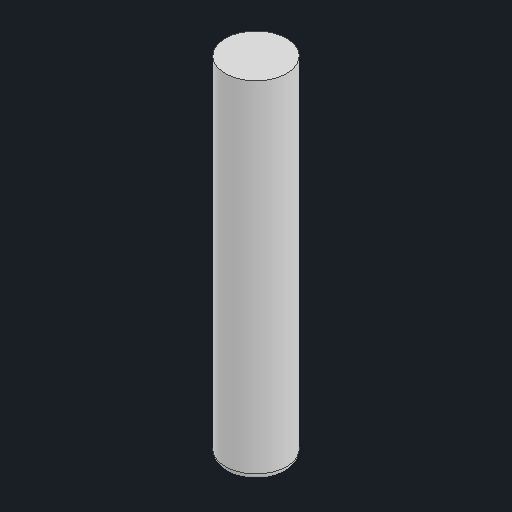
# Autodesk Inventor part: thigh-bone
Saved by Autodesk Inventor 2026.2 (Build 302298010, 298A)
## iProperties
Created: 2026-10-22
Part Number: thigh-bone
Material: Generic
Document SubType Name: Modeling
Designer: user
Density: 1 g/cm^3
Appearance: Default
Mass: 119.992 g
Surface Area: 173.105 cm^2
Volume: 119.992 cm^3
Author: user
Autodesk Inventor part; units mm, degrees
ref_plane "YZ Plane" through (0, 0, 0) normal (1, 0, 0) x (0, 1, 0)
ref_plane "XZ Plane" through (0, 0, 0) normal (0, 1, 0) x (-1, 0, 0)
ref_plane "XY Plane" through (0, 0, 0) normal (0, 0, 1) x (1, 0, 0)
sketch "Sketch1" plane through (0, 0, 0) normal (0, 0, 1) x (1, 0, 0)
  line L0 (0, 0) -> (10, 0)
  line L1 (10, 0) -> (10, 105)
  line L2 (10, 105) -> (0, 105)
  line L3 (0, 105) -> (0, 0)
  dimension "d0" = 10
  dimension "d1" = 105
  constraints: 8 end point, 2 parallel, 1 horizontal, 1 perpendicular
  measures "d0" distance of L0.start L0.end
  measures "d1" distance of L2.end L0.start
extrude "Extrusion1" [suppressed]
sketch "S7_bone" plane through (0, 0, 0) normal (0, 0, 1) x (1, 0, 0)
  line L0 (0, 10) -> (15, 10)
  line L1 (15, 10) -> (15, 180)
  line L2 (15, 180) -> (0, 180)
  line L3 (0, 180) -> (0, 10)
  line L4 (0, -24) -> (0, 214) projected
  constraints: 8 end point
revolve "Bone_D30" add sketch "S7_bone" angle 360 about axis through (0, -10, 0) along (0, 1, 0) separate body
fillet "Joint_end_R3" radius 3 1 edges at (-15, 10, 0)
body "Solid1"
body "Solid2"
